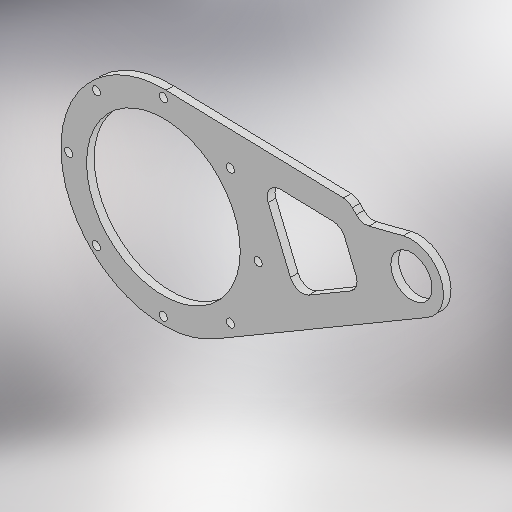
# Autodesk Inventor part: CP4.0_base-arm2
Saved by Autodesk Inventor 2025.3 (Build 293356030, 356C)
## iProperties
Created: 2026-01-04
Part Number: CP4.0_base-arm2
Material: 一般
Document SubType Name: Sheet Metal
Designer: ibuki_ono
Density: 1 g/cm^3
Sheet Metal Rule: Default_mm
Appearance: 既定
Author: ibuki_ono
Autodesk Inventor part; units mm, degrees
ref_plane "YZ Plane" through (0, 0, 0) normal (1, 0, 0) x (0, 1, 0)
ref_plane "XZ Plane" through (0, 0, 0) normal (0, 1, 0) x (-1, 0, 0)
ref_plane "XY Plane" through (0, 0, 0) normal (0, 0, 1) x (1, 0, 0)
sketch "スケッチ1" plane through (0, 0, 0) normal (0, 0, 1) x (1, 0, 0)
  circle A0 centre (0, 0) radius 40
  circle A1 centre (96.8246, 25) radius 12.5
  line L0 (1.0363, 39.9866) -> (97.1484, 37.4958)
  line L1 (103.1574, 14.2229) -> (20.2651, -34.4866)
  dimension "d0" = 80
  dimension "d1" = 25
  dimension "d2" = 100
  dimension "d34" = 25
  measures "d0" diameter of A0
  measures "d1" diameter of A1
  measures "d2" distance of point (0, 0) A1.centre
  measures "d34" vertical distance of point (0, 0) A1.centre
extrude "プレート1" add sketch "スケッチ1" along normal blind 3
sketch "スケッチ2" plane through (0, 0, 3) normal (0, 0, 1) x (1, 0, 0)
  line L0 (0, 0) -> (37, 0) construction
  line L1 (0, 0) -> (37, 0) construction
  dimension "d4" = 37
  dimension "d5" = 0
  constraints: 4 end point, 2 horizontal, 1 coincident, 1 collinear
  measures "d4" distance of L0.start L0.end
  measures "d5" distance between parallel lines of L0 L1
hole "穴1" at (37, 0, 3) direction (0, 0, -1) diameter 3.2 end through all
pattern_circular "円形状パターン1" count 8 over 360 about axis through (0, 0, -10) along (0, 0, 1) of "穴1"
sketch "スケッチ4" plane through (0, 0, 3) normal (0, 0, 1) x (1, 0, 0)
  circle A0 centre (0, 0) radius 30
  dimension "d28" = 60
  constraints: 1 centre point, 1 coincident
  measures "d28" diameter of A0
extrude "押し出し1" cut sketch "スケッチ4" against normal blind 10
sketch "スケッチ5" plane through (0, 0, 3) normal (0, 0, 1) x (1, 0, 0)
  arc A0 (103.1574, 14.2229) -> (97.1484, 37.4958) centre (96.8246, 25) ccw projected
  circle A1 centre (96.8246, 25) radius 8.05
  point P0 (0, 0)
  dimension "d31" = 16.1
  constraints: 1 centre point, 1 coincident
  measures "d31" diameter of A1
extrude "押し出し2" cut sketch "スケッチ5" against normal through all
sketch "スケッチ6" plane through (0, 0, 3) normal (0, 0, 1) x (1, 0, 0)
  arc A0 (103.1574, 14.2229) -> (97.1484, 37.4958) centre (96.8246, 25) ccw projected
  line L0 (1.0363, 39.9866) -> (97.1484, 37.4958) projected
  line L1 (103.1574, 14.2229) -> (20.2651, -34.4866) projected
  line L2 (20.2651, -34.4866) -> (103.1574, 14.2229) projected
  circle A1 centre (96.8246, 25) radius 12.5
  line L3 (96.8246, 25) -> (0, 0) construction
  line L4 (72.3729, 38.1379) -> (77.3609, 32.8844)
  line L5 (77.3609, 32.8844) -> (93.6996, 37.1031)
  point P0 (103.1574, 14.2229)
  dimension "d35" = 45
  dimension "d37" = 21
  constraints: 6 end point, 1 coincident, 1 parallel, 1 point on line, 5 other
  measures "d35" angle of L0 L4
  measures "d37" distance of A0.centre L4.end
extrude "押し出し3" cut sketch "スケッチ6" against normal through all contours L5 L4 L0 A1
fillet "フィレット1" radius 5 2 edges at (77.3609, 32.8844, 1.5) (72.3729, 38.1379, 1.5)
sketch "スケッチ7" plane through (0, 0, 3) normal (0, 0, 1) x (1, 0, 0)
  line L0 (1.0363, 39.9866) -> (70.3025, 38.1915) projected
  line L1 (103.1574, 14.2229) -> (20.2651, -34.4866) projected
  line L2 (37.9657, 29.0262) -> (51.7948, -4.3603)
  line L3 (51.7948, -4.3603) -> (76.8983, 10.3912)
  line L4 (76.8983, 10.3912) -> (69.5182, 28.2085)
  line L5 (69.5182, 28.2085) -> (37.9657, 29.0262)
  circle A0 centre (26.163, 26.163) radius 1.6 projected
  circle A1 centre (37, 0) radius 1.6 projected
  line L6 (26.163, 26.163) -> (37, 0) construction
  circle A2 centre (96.8246, 25) radius 8.05 construction
  point P0 (0, 0)
  dimension "d42" = 10
  dimension "d43" = 10
  dimension "d44" = 12
  dimension "d45" = 24
  constraints: 10 end point, 4 parallel
  measures "d42" distance between parallel lines of L0 L5
  measures "d43" distance between parallel lines of L1 L3
  measures "d44" distance from line of L6.start L2
  measures "d45" distance from line of A2.centre L4
extrude "押し出し4" cut sketch "スケッチ7" against normal through all contours L5 L4 L3 L2
fillet "フィレット2" radius 5 4 edges at (37.9657, 29.0262, 1.5) (69.5182, 28.2085, 1.5) (76.8983, 10.3912, 1.5) (51.7948, -4.3603, 1.5)
equation "\"d11\" = Thickness"
equation "\"d43\" = d42"
equation "\"d3\" = Thickness"
equation "\"BendRadius\" = Thickness"
equation "\"BendReliefWidth\" = Thickness"
equation "\"BendReliefDepth\" = 0.5 * Thickness"
equation "\"CornerReliefSize\" = 4 * Thickness"
equation "\"MinimumRemnant\" = 2 * Thickness"
equation "\"TransitionRadius\" = BendRadius"
equation "\"JacobiRadiusSize\" = BendRadius"
equation "\"GapSize\" = Thickness"
equation "\"Thickness\" = 3"
